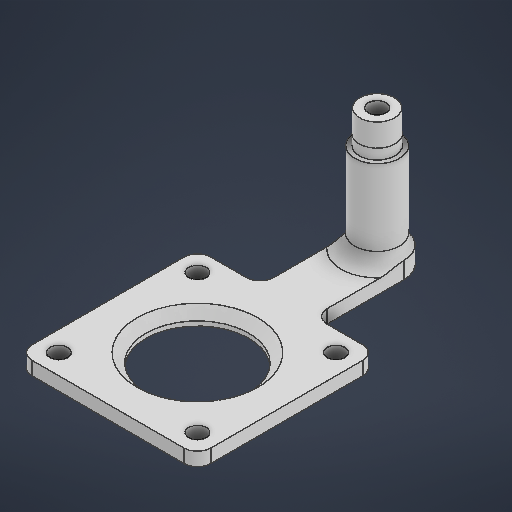
# Autodesk Inventor part: 5_v2
Saved by Autodesk Inventor 2026.2 (Build 302298010, 298A)
## iProperties
Created: 2026-03-20
Part Number: 5_v2
Material: 일반
Document SubType Name: Modeling
Designer: work
Density: 1 g/cm^3
Appearance: 기본값
Author: work
Autodesk Inventor part; units mm, degrees
ref_plane "YZ Plane" through (0, 0, 0) normal (1, 0, 0) x (0, 1, 0)
ref_plane "XZ Plane" through (0, 0, 0) normal (0, 1, 0) x (-1, 0, 0)
ref_plane "XY Plane" through (0, 0, 0) normal (0, 0, 1) x (1, 0, 0)
sketch "스케치1" plane through (0, 0, 0) normal (0, 1, 0) x (-1, 0, 0)
  line L0 (-15.5, 15.5) -> (15.5, 15.5) construction
  line L1 (15.5, 15.5) -> (15.5, -15.5) construction
  line L2 (15.5, -15.5) -> (-15.5, -15.5) construction
  line L3 (-15.5, -15.5) -> (-15.5, 15.5) construction
  line L4 (-15.5, 15.5) -> (15.5, -15.5) construction
  line L5 (15.5, 15.5) -> (-15.5, -15.5) construction
  circle A0 centre (15.5, 15.5) radius 2
  circle A1 centre (15.5, -15.5) radius 2
  circle A2 centre (-15.5, -15.5) radius 2
  circle A3 centre (-15.5, 15.5) radius 2
  circle A4 centre (0, 0) radius 11.5
  line L6 (-20, 20) -> (20, 20)
  line L7 (20, 20) -> (20, -20)
  line L8 (20, -20) -> (-20, -20)
  line L9 (-20, -20) -> (-20, 20)
  line L10 (-20, 20) -> (20, -20) construction
  line L11 (20, 20) -> (-20, -20) construction
  line L12 (0, 0) -> (0, -40.2) construction
  circle A5 centre (0, -40.2) radius 6
  line L13 (6, -40.2) -> (-6, -40.2) construction
  line L14 (6, -40.2) -> (6, -20)
  line L15 (-6, -40.2) -> (-6, -20)
  circle A6 centre (0, -40.2) radius 5
  circle A7 centre (0, -40.2) radius 2
  circle A8 centre (0, -40.2) radius 4
  dimension "d0" = 31
  dimension "d1" = 31
  dimension "d2" = 4
  dimension "d3" = 4
  dimension "d4" = 4
  dimension "d5" = 4
  dimension "d6" = 23
  dimension "d7" = 40
  dimension "d8" = 40
  dimension "d10" = 40.2
  dimension "d11" = 12
  dimension "d14" = 10
  dimension "d15" = 8
  dimension "d16" = 4
  dimension "d17" = 12
  constraints: 32 end point, 10 coincident, 9 centre point, 4 midpoint, 4 parallel, 4 perpendicular, 2 horizontal, 2 point on circle, 2 point on line, 1 vertical
  measures "d0" distance of L1.end L5.end
  measures "d1" distance of L0.end L1.end
  measures "d2" diameter of A0
  measures "d3" diameter of A1
  measures "d4" diameter of A2
  measures "d5" diameter of A3
  measures "d6" diameter of A4
  measures "d7" distance of L7.end L11.end
  measures "d8" distance of L7.start L7.end
  measures "d10" distance of L12.start L12.end
  measures "d11" distance between parallel lines of L15 L14
  measures "d14" diameter of A6
  measures "d15" diameter of A8
  measures "d16" diameter of A7
  measures "d17" diameter of A5
extrude "돌출1" add sketch "스케치1" along normal blind 3 contours L6 L7 L8 L9 | L8 L14 A5 L15
extrude "돌출2" add sketch "스케치1" along normal blind 3 contours A5
extrude "돌출3" add sketch "스케치1" along normal blind 23 contours A6
extrude "돌출4" add sketch "스케치1" along normal blind 30.3 contours A8
chamfer "모따기1" distance 5 angle 1 1 edges at (4, 30.3, -40.2) measured on face at (4, 29.8, -40.2)
sketch "스케치2" plane through (-6, 0, -20) normal (0, 0, -1) x (-1, 0, 0)
  point P0 (-6, 0)
fillet "모깎기1" radius 3 7 edges at (-6, 1.5, -20) (-20, 1.5, -20) (5, 3, -40.2) (6, 1.5, -20) (20, 1.5, -20) (20, 1.5, 20) (-20, 1.5, 20)
chamfer "모따기2" distance 2 angle 45 1 edges at (11.5, 3, 0)
